enclosure-base (Autodesk Fusion 360 design; units mm, degrees)
part number: 2026-11-27-19-35-51-728
Autodesk Fusion 360 part; units mm, degrees
sketch "Sketch1" plane through (0, 0, 0) normal (0, 1, 0) x (1, 0, 0)
  line L0 (70, 200) -> (-70, 200)
  line L1 (-70, 200) -> (-70, -200)
  line L2 (-70, -200) -> (70, -200)
  line L3 (70, -200) -> (70, 200)
  line L4 (70, 200) -> (-70, -200) construction
  line L5 (-70, 200) -> (70, -200) construction
  dimension "d1" = 140
  dimension "d2" = 400
  constraint horizontal L0
  constraint perpendicular L0 L1
  constraint parallel L0 L2
  constraint parallel L1 L3
  constraint coincident L4 origin
  constraint coincident L5 origin
  measures "d1" distance of L1.end L2.end
extrude "Extrude1" add sketch "Sketch1" along normal blind 3
sketch "Sketch2" plane through (0, 0, 0) normal (1, 0, 0) x (0, 0, -1)
sketch "Sketch3" plane through (0, 3, 0) normal (0, 1, 0) x (-1, 0, 0)
  line L0 (-70, 200) -> (-70, -200)
  line L1 (-70, -200) -> (70, -200)
  line L2 (70, -200) -> (70, 200)
  line L3 (70, 200) -> (-70, 200)
  line L4 (-67, 197) -> (-70, 197)
  line L5 (-70, 197) -> (-70, -197)
  line L6 (-70, -197) -> (-67, -197)
  line L7 (-67, -197) -> (-67, 197)
  line L8 (-67, 197) -> (-70, -197) construction
  line L9 (-70, 197) -> (-67, -197) construction
  line L10 (67, -197) -> (67, 197)
  line L11 (70, 197) -> (70, -197)
  line L12 (67, 197) -> (70, 197)
  line L13 (70, -197) -> (67, -197)
  point P0 (-68.5, 0)
  dimension "d5" = 3
  dimension "d6" = 394
  constraint horizontal L4
  constraint perpendicular L4 L5
  constraint parallel L4 L6
  constraint parallel L5 L7
  constraint coincident L8 P0
  constraint coincident L9 P0
  measures "d5" distance of L5.end L6.end
  measures "d6" distance of L4.end L5.end
extrude "Extrude2" add sketch "Sketch3" along normal blind 140 contours L0 L4 L5 L6 L7 | L2 L10 L11 L12 L13
sketch "Sketch4" plane through (-67, 0, 0) normal (1, 0, 0) x (0, 0, -1)
  line L0 (-197, 3) -> (197, 3)
  line L1 (197, 3) -> (197, 143)
  line L2 (197, 143) -> (-197, 143)
  line L3 (-197, 143) -> (-197, 3)
  line L4 (83, 137) -> (77, 137)
  line L5 (77, 137) -> (77, 149)
  line L6 (77, 149) -> (83, 149)
  line L7 (83, 149) -> (83, 137)
  line L8 (83, 137) -> (77, 149) construction
  line L9 (77, 137) -> (83, 149) construction
  line L10 (-152, 137) -> (-158, 137)
  line L11 (-158, 137) -> (-158, 149)
  line L12 (-158, 149) -> (-152, 149)
  line L13 (-152, 149) -> (-152, 137)
  line L14 (-152, 137) -> (-158, 149) construction
  line L15 (-158, 137) -> (-152, 149) construction
  point P0 (80, 143)
  point P1 (-155, 143)
  dimension "d11" = 6
  dimension "d12" = 12
  dimension "d13" = 6
  dimension "d14" = 12
  constraint horizontal L4
  constraint perpendicular L4 L5
  constraint parallel L4 L6
  constraint parallel L5 L7
  constraint coincident L8 P0
  constraint coincident L9 P0
  constraint horizontal L10
  constraint perpendicular L10 L11
  constraint parallel L10 L12
  constraint parallel L11 L13
  constraint coincident L14 P1
  constraint coincident L15 P1
  measures "d11" distance of L5.end L6.end
  measures "d12" distance of L4.end L5.end
  measures "d13" distance of L11.end L12.end
  measures "d14" distance of L10.end L11.end
extrude "Extrude3" cut sketch "Sketch4" against normal blind 3 contours L2 L10 L11 L13 | L2 L4 L5 L7
